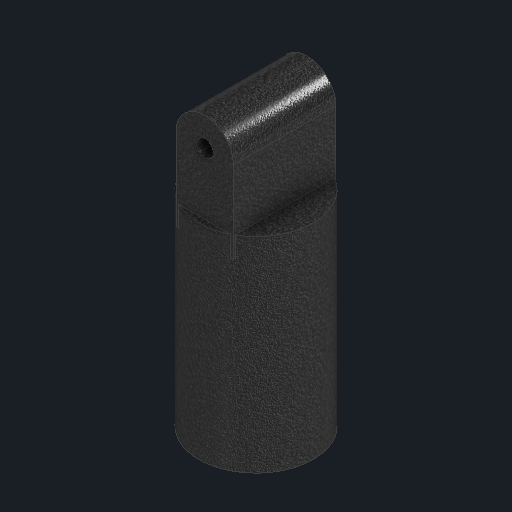
# Autodesk Inventor part: tripod_leg_top
Saved by Autodesk Inventor 2027.1 (Build 311270010, 270A)
## iProperties
Created: 2026-11-03
Part Number: tripod_leg_top
Material: Generic
Description: Tripod leg hinge casting
Document SubType Name: Modeling
Designer: Claude (from photos)
Density: 1 g/cm^3
Appearance: Black Cast
Author: alexg
Autodesk Inventor part; units mm, degrees
ref_plane "YZ Plane" through (0, 0, 0) normal (1, 0, 0) x (0, 1, 0)
sketch "Hinge block sketch" plane through (0, 0, 0) normal (0, 0, 1) x (1, 0, 0)
  line L0 (-14, -40) -> (14, -40)
  line L1 (14, -40) -> (14, 0)
  line L2 (14, 0) -> (-14, 0)
  line L3 (-14, 0) -> (-14, -40)
  constraints: 8 end point, 2 parallel, 1 horizontal, 1 perpendicular
extrude "Hinge block" add sketch "Hinge block sketch" along normal mid plane 50
sketch "Hinge boss sketch" plane through (0, 0, 0) normal (0, 0, 1) x (1, 0, 0)
  circle A0 centre (0, 0) radius 14
  constraints: 1 centre point
extrude "Hinge boss" add sketch "Hinge boss sketch" along normal mid plane 50
ref_plane "Work Plane1" through (0, -30, 0) normal (0, 1, 0) x (-1, 0, 0)
sketch "Leg sleeve sketch" plane through (0, -30, 0) normal (0, 1, 0) x (-1, 0, 0)
  circle A0 centre (0, 0) radius 28
  constraints: 1 centre point
extrude "Leg sleeve" add sketch "Leg sleeve sketch" against normal blind 100
ref_plane "Work Plane2" through (0, 0, 30) normal (0, 0, 1) x (1, 0, 0)
sketch "Hinge pin hole sketch" plane through (0, 0, 30) normal (0, 0, 1) x (1, 0, 0)
  circle A0 centre (0, 0) radius 4
  constraints: 1 centre point
extrude "Hinge pin hole" cut sketch "Hinge pin hole sketch" against normal blind 60
body "Solid1"
